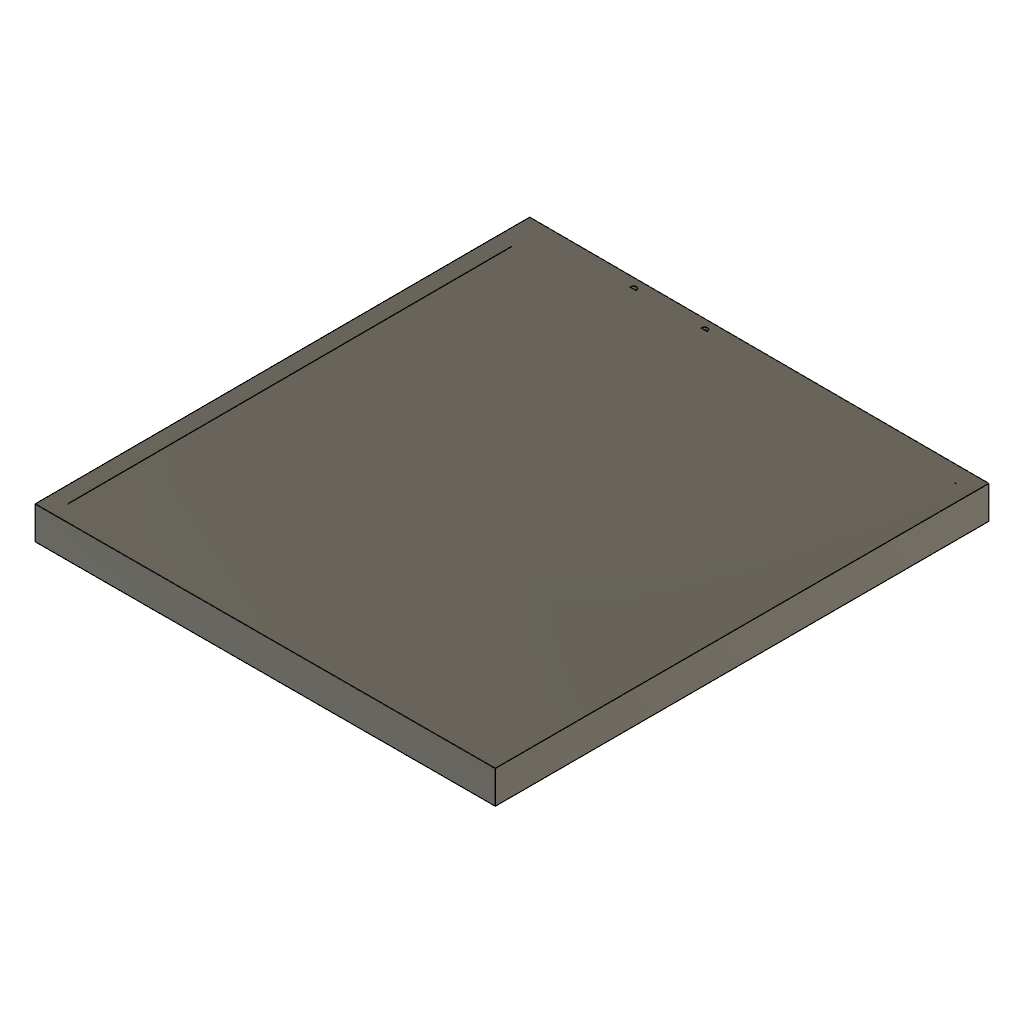
Enclosure3D (Autodesk Fusion 360 archive; units mm, degrees)
design "Tapa"
Autodesk Fusion 360 part; units mm, degrees
derive "DerivedContext1" from "Enclosure3D v3"
sketch "sketch 235" plane through (0, 0, 8.090043) normal (0, 0, 1) x (-1, 0, 0)
  arc A0 (52.549301, -88.637389) -> (52.524439, -88.507828) centre (52.199289, -88.637389) ccw
  line L0 (52.549301, -88.637389) -> (52.549301, -89.337363)
  arc A1 (51.849276, -89.337363) -> (52.549301, -89.337363) centre (52.199289, -89.337363) ccw
  line L1 (51.849276, -89.337363) -> (51.849276, -88.637389)
  arc A2 (51.874729, -88.506355) -> (51.849276, -88.637389) centre (52.199289, -88.637389) ccw
  line L2 (51.874729, -88.506355) -> (43.875739, -88.488217)
  arc A3 (43.909119, -88.637389) -> (43.875739, -88.488217) centre (43.559106, -88.637389) ccw
  line L3 (43.909119, -88.637389) -> (43.909119, -89.337363)
  arc A4 (43.209093, -89.337363) -> (43.909119, -89.337363) centre (43.559106, -89.337363) ccw
  line L4 (43.209093, -89.337363) -> (43.209093, -88.637389)
  arc A5 (43.243153, -88.486782) -> (43.209093, -88.637389) centre (43.559106, -88.637389) ccw
  line L5 (43.243153, -88.486782) -> (12.04572, -88.41604)
  line L6 (12.04572, -88.41604) -> (12.04572, -32.361202)
  line L7 (12.04572, -32.361202) -> (63.904793, -32.243608)
  line L8 (63.904793, -32.243608) -> (64.027432, -85.346495)
  line L9 (64.027432, -85.346495) -> (64.027432, -88.533912)
  line L10 (64.027432, -88.533912) -> (52.524439, -88.507828)
  line L11 (65.900173, -30.239078) -> (10.04572, -30.365732)
  line L12 (10.04572, -30.365732) -> (10.04572, -90.41151)
  line L13 (10.04572, -90.41151) -> (66.027432, -90.538452)
  line L14 (66.027432, -90.538452) -> (66.027432, -85.344185)
  line L15 (66.027432, -85.344185) -> (65.900432, -30.35309)
  line L16 (65.900432, -30.35309) -> (65.900173, -30.239078)
extrude "Extruir1" add sketch "sketch 235" along normal blind 2 contours L11 L12 L13 L14 L15 L16 picked at (10.712387, -51.046148)
extrude "Extruir2" add 1 faces at (-29.332078, 32.322004, 8.75671) along direction (-0.00226757, 0.99999743, 0) blind 57
extrude "Extruir3" add 1 faces at (-12.04572, 69.731094, 8.75671) along direction (-1, 0, 0) blind 45
extrude "Extruir4" add 1 faces at (-39.053202, 50.633341, 10.090043) along direction (0, 0, -1) blind 2
sketch "sketch 730" plane through (0, 0, 8.090043) normal (0, 0, -1) x (1, 0, 0)
  line L0 (-63.904793, -32.243608) -> (-64.027432, -86.327611)
  line L1 (-64.027432, -86.327611) -> (-64.027432, -85.346495)
  line L2 (-64.027432, -85.346495) -> (-63.904793, -32.243608)
  line L3 (-65.900173, -30.239078) -> (-65.900432, -30.35309)
  line L4 (-65.900432, -30.35309) -> (-66.027432, -85.344185)
  line L5 (-66.027432, -85.344185) -> (-66.027432, -90.538452)
  line L6 (-66.027432, -90.538452) -> (-10.04572, -90.41151)
  line L7 (-10.04572, -90.41151) -> (-10.04572, -30.365732)
  line L8 (-10.04572, -30.365732) -> (-65.900173, -30.239078)
  line L9 (-51.849276, -89.271091) -> (-51.849276, -89.337363)
  arc A0 (-52.549301, -89.337363) -> (-51.849276, -89.337363) centre (-52.199289, -89.337363) ccw
  line L10 (-52.549301, -89.337363) -> (-52.549301, -89.269504)
  line L11 (-52.549301, -89.269504) -> (-51.849276, -89.271091)
  line L12 (-43.209093, -89.290683) -> (-43.209093, -89.337363)
  arc A1 (-43.909119, -89.337363) -> (-43.209093, -89.337363) centre (-43.559106, -89.337363) ccw
  line L13 (-43.909119, -89.337363) -> (-43.909119, -89.289096)
  line L14 (-43.909119, -89.289096) -> (-43.209093, -89.290683)
  line L15 (-12.172829, -88.41604) -> (-12.04572, -88.41604)
  line L16 (-12.04572, -88.41604) -> (-12.172829, -88.416328)
  line L17 (-12.172829, -88.416328) -> (-12.172829, -88.41604)
  line L18 (-64.527432, -89.035047) -> (-11.54572, -88.914907)
  line L19 (-11.54572, -88.914907) -> (-11.54572, -31.862334)
  line L20 (-11.54572, -31.862334) -> (-64.403637, -31.742475)
  line L21 (-64.403637, -31.742475) -> (-64.527432, -85.345917)
  line L22 (-64.527432, -85.345917) -> (-64.527432, -89.035047)
extrude "Extruir5" add sketch "sketch 730" along normal blind 2 contours L3 L4 L5 L6 L7 L8 picked at (-10.54572, -50.879859)
